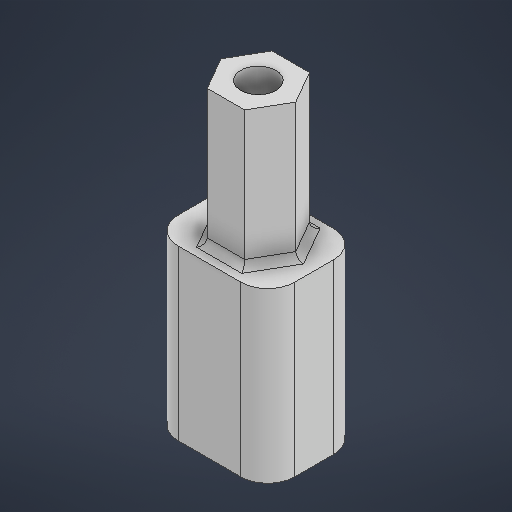
# Autodesk Inventor part: Union entre motor
Saved by Autodesk Inventor 2027.1 (Build 311270010, 270A)
## iProperties
Created: 2026-09-19
Part Number: Union entre motor
Material: Genérico
Document SubType Name: Modeling
Designer: irene
Density: 1 g/cm^3
Appearance: Valor por defecto
Author: irene
Autodesk Inventor part; units mm, degrees
ref_plane "YZ Plane" through (0, 0, 0) normal (1, 0, 0) x (0, 1, 0)
ref_plane "XZ Plane" through (0, 0, 0) normal (0, 1, 0) x (-1, 0, 0)
ref_plane "XY Plane" through (0, 0, 0) normal (0, 0, 1) x (1, 0, 0)
sketch "Boceto1" plane through (0, 0, 0) normal (0, 1, 0) x (-1, 0, 0)
  line L0 (0, 0) -> (5.4, 0)
  line L1 (5.4, 0) -> (5.4, 3.76)
  line L2 (5.4, 3.76) -> (0, 3.76)
  line L3 (0, 3.76) -> (0, 0)
  dimension "d0" = 5.4
  dimension "d1" = 3.76
  constraints: 8 end point, 2 parallel, 1 horizontal, 1 perpendicular
  measures "d0" distance of L1.end L2.end
  measures "d1" distance of L0.end L1.end
extrude "Extrusión1" add sketch "Boceto1" along normal blind 7.59
sketch "Boceto2" plane through (0, 7.59, 0) normal (0, 1, 0) x (1, 0, 0)
  line L0 (-5.4, 0) -> (-5.4, -3.76) projected
  line L1 (-5.4, -1.88) -> (0, -1.88) construction
  line L2 (0, -3.76) -> (0, 0) projected
  line L3 (-5.4, -3.76) -> (0, -3.76) projected
  line L4 (-2.7, -3.76) -> (-2.7, 0) construction
  line L5 (0, 0) -> (-5.4, 0) projected
  circle A0 centre (-2.7, -1.88) radius 1.3
  dimension "d4" = 2.6
  constraints: 5 midpoint, 4 end point, 1 centre point
  measures "d4" diameter of A0
extrude "Extrusión2" cut sketch "Boceto2" against normal through all contours A0
sketch "Boceto3" plane through (0, 0, 0) normal (0, -1, 0) x (1, 0, 0)
  circle A0 centre (-2.7, 1.88) radius 1.3 projected
  line L0 (0, 0) -> (-5.4, 0) projected
  line L1 (0, 3.76) -> (0, 0) projected
  line L2 (-5.4, 3.76) -> (0, 3.76) projected
  line L3 (-5.4, 0) -> (-5.4, 3.76) projected
  arc A1 (-0.5, -1.5) -> (1.5, 0.5) centre (-0.5, 0.5) ccw
  line L4 (-0.5, -1.5) -> (-5.13, -1.5)
  arc A2 (-7.13, 0.5) -> (-5.13, -1.5) centre (-5.13, 0.5) ccw
  line L5 (-7.13, 0.5) -> (-7.13, 3.38)
  arc A3 (-5.13, 5.38) -> (-7.13, 3.38) centre (-5.13, 3.38) ccw
  line L6 (-5.13, 5.38) -> (-0.5, 5.38)
  arc A4 (1.5, 3.38) -> (-0.5, 5.38) centre (-0.5, 3.38) ccw
  line L7 (1.5, 3.38) -> (1.5, 0.5)
  dimension "d8" = 1.5
  constraints: 8 end point, 8 point on circle, 4 centre point
  measures "d8" distance between parallel lines of L1 L7
extrude "Extrusión3" add sketch "Boceto3" against normal blind 10 contours A0 | L0 L3 L2 L1 | L4 A2 L5 A3 L6 A4 L7 A1
sketch "Boceto4" plane through (0, 7.59, 0) normal (0, 1, 0) x (1, 0, 0)
  arc A0 (-5.13, 0) -> (-5.63, -0.5) centre (-5.13, -0.5) ccw projected
  line L0 (-5.63, -0.5) -> (-5.63, -3.38) projected
  arc A1 (-5.63, -3.38) -> (-5.13, -3.88) centre (-5.13, -3.38) ccw projected
  line L1 (-5.13, -3.88) -> (-0.5, -3.88) projected
  arc A2 (-0.5, -3.88) -> (0, -3.38) centre (-0.5, -3.38) ccw projected
  line L2 (0, -3.38) -> (0, -0.5) projected
  arc A3 (0, -0.5) -> (-0.5, 0) centre (-0.5, -0.5) ccw projected
  line L3 (-0.5, 0) -> (-5.13, 0) projected
  circle A4 centre (-2.815, -1.94) radius 1.225 projected
  point P0 (0, 0)
extrude "Extrusión4" add sketch "Boceto4" along normal up to surface (2.41 mm away)
extrude "Extrusión5" cut sketch "Boceto3" against normal blind 7.59 contours L0 L3 L2 L1
sketch "Boceto5" plane through (-2.7, 0, 1.88) normal (0, -1, 0) x (1, 0, 0)
  circle A0 centre (0, 0) radius 1.3 projected
  point P0 (2.7, -1.88)
extrude "Extrusión6" cut sketch "Boceto5" against normal through all
sketch "Boceto6" plane through (0, 7.59, 0) normal (0, -1, 0) x (1, 0, 0)
  circle A0 centre (-2.7, 1.88) radius 1.3 projected
  line L0 (-0.5, -1.5) -> (-5.13, -1.5) projected
  arc A1 (-7.13, 0.5) -> (-5.13, -1.5) centre (-5.13, 0.5) ccw projected
  line L1 (-7.13, 0.5) -> (-7.13, 3.38) projected
  arc A2 (-5.13, 5.38) -> (-7.13, 3.38) centre (-5.13, 3.38) ccw projected
  line L2 (-5.13, 5.38) -> (-0.5, 5.38) projected
  arc A3 (1.5, 3.38) -> (-0.5, 5.38) centre (-0.5, 3.38) ccw projected
  line L3 (1.5, 3.38) -> (1.5, 0.5) projected
  arc A4 (-0.5, -1.5) -> (1.5, 0.5) centre (-0.5, 0.5) ccw projected
  point P0 (0, 0)
extrude "Extrusión7" add sketch "Boceto6" against normal blind 12.5
sketch "Boceto9" plane through (0, 7.59, 0) normal (0, -1, 0) x (1, 0, 0)
  line L0 (-0.32, 1.88) -> (-1.51, 3.9411) construction
  line L1 (-5.4, 3.76) -> (0, 3.76) projected
  line L2 (-5.4, 0) -> (-5.4, 3.76) projected
  line L3 (0, 0) -> (-5.4, 0) projected
  line L4 (0, 3.76) -> (0, 0) projected
  circle A0 centre (-2.7, 1.88) radius 1.3 projected
extrude "Extrusión10" cut sketch "Boceto9" against normal blind 7.59
sketch "Boceto10" plane through (0, 0, 0) normal (0, -1, 0) x (1, 0, 0)
  line L0 (-5.13, -1.5) -> (-0.5, -1.5) projected
  arc A0 (-0.5, -1.5) -> (1.5, 0.5) centre (-0.5, 0.5) ccw projected
  line L1 (1.5, 0.5) -> (1.5, 3.38) projected
  arc A1 (1.5, 3.38) -> (-0.5, 5.38) centre (-0.5, 3.38) ccw projected
  line L2 (-0.5, 5.38) -> (-5.13, 5.38) projected
  arc A2 (-5.13, 5.38) -> (-7.13, 3.38) centre (-5.13, 3.38) ccw projected
  line L3 (-7.13, 3.38) -> (-7.13, 0.5) projected
  arc A3 (-7.13, 0.5) -> (-5.13, -1.5) centre (-5.13, 0.5) ccw projected
  line L4 (-5.4, 0) -> (-5.4, 3.76) projected
  line L5 (-5.4, 3.76) -> (0, 3.76) projected
  line L6 (0, 3.76) -> (0, 0) projected
  line L7 (0, 0) -> (-5.4, 0) projected
extrude "Extrusión11" cut sketch "Boceto10" against normal blind 7.59
sketch "Boceto11" plane through (0, 20.09, 0) normal (0, 1, 0) x (1, 0, 0)
  circle A0 centre (-2.7, -1.88) radius 1.3 projected
  line L0 (0, -3.76) -> (-5.4, -3.76) construction
  line L1 (-2.7, -1.88) -> (0.075, -1.88)
  line L2 (-2.7, -1.88) -> (-5.475, -1.88)
  line L3 (-2.7, -1.88) -> (-1.3125, -4.2832)
  line L4 (-2.7, -1.88) -> (-4.0875, 0.5232)
  line L5 (-2.7, -1.88) -> (-1.3125, 0.5232)
  line L6 (-2.7, -1.88) -> (-4.0875, -4.2832)
  line L7 (-1.3125, 0.5232) -> (0.075, -1.88)
  line L8 (-1.3125, -4.2832) -> (0.075, -1.88)
  line L9 (-1.3125, 0.5232) -> (-4.0875, 0.5232)
  line L10 (-4.0875, 0.5232) -> (-5.475, -1.88)
  line L11 (-5.475, -1.88) -> (-4.0875, -4.2832)
  line L12 (-5.4, -3.76) -> (-5.4, 0) projected
  line L13 (-1.3125, -4.2832) -> (-4.0875, -4.2832)
  point P0 (0, 0)
  point P1 (-5.4, -2.0099)
  point P2 (-5.4, -1.7501)
  dimension "d45" = 2.775
  dimension "d46" = 2.775
  dimension "d48" = 2.775
  dimension "d49" = 2.775
  dimension "d50" = 2.775
  dimension "d51" = 2.775
  dimension "d57" = 60
  dimension "d58" = 60
  dimension "d59" = 60
  dimension "d60" = 60
  constraints: 24 end point, 2 horizontal
  measures "d45" distance of L1.start L1.end
  measures "d46" distance of L1.start L2.end
  measures "d48" distance of L1.start L3.end
  measures "d49" distance of L1.start L4.end
  measures "d50" distance of L1.start L5.end
  measures "d51" distance of L1.start L6.end
  measures "d57" angle of L2 L4
  measures "d58" angle of L2 L6
  measures "d59" angle of L1 L3
  measures "d60" angle of L5 L1
extrude "Extrusión12" add sketch "Boceto11" along normal blind 10.1 contours L1 L8 L3 A0 | A0 L5 L7 L1 | A0 L4 L9 L5 | L3 L13 L6 A0 | A0 L2 L12 L10 L4 | L6 L11 L12 L2 A0 | L12 L11 L2 | L2 L10 L12
fillet "Empalme2" radius 0.5 6 edges at (-4.7812, 20.09, 3.0816) (-2.7, 20.09, 4.2832) (-4.7812, 20.09, 0.6784) (-2.7, 20.09, -0.5232) (-0.6187, 20.09, 0.6784) (-0.6187, 20.09, 3.0816)
